DRR_base_section_simple (Autodesk Fusion 360 design; units mm, degrees)
part number: 2026-11-05-15-11-21-307
part number: 2026-11-05-15-14-36-906
part number: 2026-11-05-15-14-36-939
part number: 2026-11-05-15-14-37-558
part number: 2026-11-05-15-14-38-707
part number: 2026-11-05-15-14-40-350
part number: 2026-11-05-15-14-40-384
part number: 2026-11-05-15-14-41-040
part number: 2026-11-05-15-14-42-462
Autodesk Fusion 360 part; units mm, degrees
sketch "Sketch1" plane through (0, 0, 0) normal (1, 0, 0) x (0, 0, -1) in component "Simple Core R"
  line L0 (-488, 329) -> (-588, 329)
  line L1 (-588, 329) -> (-588, 379)
  line L2 (-588, 379) -> (-488, 379)
  line L3 (-488, 379) -> (-488, 329)
  line L4 (-490, 331) -> (-586, 331)
  line L5 (-586, 331) -> (-586, 377)
  line L6 (-586, 377) -> (-490, 377)
  line L7 (-490, 377) -> (-490, 331)
  dimension "d249" = 329
  dimension "d251" = 379
  dimension "d253" = 331
  dimension "d255" = 377
  constraint horizontal L0.start L0.end
  constraint vertical L0.end L1.end
  constraint vertical L0.start L2.end
  constraint horizontal L1.end L2.end
  constraint horizontal L4.start L4.end
  constraint vertical L4.end L5.end
  constraint vertical L4.start L6.end
  constraint horizontal L5.end L6.end
  measures "d249" vertical distance of origin L0.start
  measures "d251" vertical distance of origin L1.end
  measures "d253" vertical distance of origin L4.start
  measures "d255" vertical distance of origin L5.end
extrude "Extrude1" add sketch "Sketch1" along normal blind 2000 makes body 1 in component "Simple Core R"
sketch "Sketch2" plane through (0, 0, 0) normal (0, 0, 1) x (1, 0, 0) in component "Simple Core R"
  circle A0 centre (50, 354) radius 5.5
  circle A1 centre (100, 354) radius 5.5
  dimension "d258" = 50
  dimension "d259" = 354
  dimension "d260" = 11
  dimension "d261" = 100
  dimension "d262" = 11
  constraint horizontal A0.centre A1.centre
  measures "d258" horizontal distance of origin A0.centre
  measures "d259" vertical distance of origin A0.centre
  measures "d260" diameter of A0
  measures "d261" horizontal distance of origin A1.centre
  measures "d262" diameter of A1
extrude "Extrude2" cut sketch "Sketch2" along normal blind 102 from surface at 487 bodies 1 in component "Simple Core R"
sketch "Sketch1 (2)" plane through (0, 0, 0) normal (1, 0, 0) x (0, 0, -1) in component "Simple Cap R"
  arc A0 (-694, 429) -> (-694, 279) centre (-228.25, 354) ccw
  line L0 (-694, 429) -> (-659, 429)
  line L1 (-659, 429) -> (-659, 382)
  line L2 (-659, 382) -> (-549, 382)
  line L3 (-549, 382) -> (-549, 326)
  line L4 (-549, 326) -> (-659, 326)
  line L5 (-659, 326) -> (-659, 279)
  line L6 (-659, 279) -> (-694, 279)
  dimension "d267" = 279
  dimension "d268" = 429
  dimension "d270" = 382
  dimension "d272" = 326
  dimension "d273" = 471.75
  constraint vertical A0.end A0.start
  constraint horizontal A0.start L0.end
  constraint vertical L0.end L1.end
  constraint horizontal L1.end L2.end
  constraint vertical L2.end L3.end
  constraint vertical L0.end L4.end
  constraint horizontal L3.end L4.end
  constraint vertical L0.end L5.end
  constraint horizontal A0.end L5.end
  measures "d267" vertical distance of origin A0.end
  measures "d268" vertical distance of origin A0.start
  measures "d270" vertical distance of origin L1.end
  measures "d272" vertical distance of origin L3.end
  measures "d273" radius of A0
extrude "Extrude1'" add sketch "Sketch1 (2)" along normal blind 1900 from surface at 100 separate body makes body 2 in component "Simple Cap R"
sketch "Sketch2 (2)" plane through (0, 0, 0) normal (1, 0, 0) x (0, 0, -1) in component "Simple Cap R"
  arc A0 (-691.4732, 426) -> (-691.4732, 282) centre (-225.25, 354) ccw
  line L0 (-691.4732, 426) -> (-659, 426)
  line L1 (-659, 426) -> (-659, 382)
  line L2 (-659, 382) -> (-549, 382)
  line L3 (-549, 382) -> (-549, 326)
  line L4 (-549, 326) -> (-659, 326)
  line L5 (-659, 326) -> (-659, 282)
  line L6 (-659, 282) -> (-691.4732, 282)
  dimension "d277" = 691.4732
  dimension "d278" = 282
  dimension "d279" = 426
  dimension "d281" = 382
  dimension "d283" = 326
  dimension "d284" = 471.75
  constraint vertical A0.end A0.start
  constraint horizontal A0.start L0.end
  constraint vertical L0.end L1.end
  constraint horizontal L1.end L2.end
  constraint vertical L2.end L3.end
  constraint vertical L0.end L4.end
  constraint horizontal L3.end L4.end
  constraint vertical L0.end L5.end
  constraint horizontal A0.end L5.end
  measures "d277" horizontal distance of origin A0.end
  measures "d278" vertical distance of origin A0.end
  measures "d279" vertical distance of origin A0.start
  measures "d281" vertical distance of origin L1.end
  measures "d283" vertical distance of origin L3.end
  measures "d284" radius of A0
extrude "Extrude2'" add sketch "Sketch2 (2)" along normal blind 100 bodies 2 in component "Simple Cap R"
sketch "Sketch3" plane through (0, 0, 0) normal (1, 0, 0) x (0, 0, -1) in component "Simple Cap R"
  line L0 (-548, 328) -> (-659, 328)
  line L1 (-659, 328) -> (-659, 380)
  line L2 (-659, 380) -> (-548, 380)
  line L3 (-548, 380) -> (-548, 328)
  dimension "d287" = 548
  dimension "d288" = 328
  dimension "d290" = 380
  constraint horizontal L0.start L0.end
  constraint vertical L0.end L1.end
  constraint vertical L0.start L2.end
  constraint horizontal L1.end L2.end
  measures "d287" horizontal distance of origin L0.start
  measures "d288" vertical distance of origin L0.start
  measures "d290" vertical distance of origin L1.end
extrude "Extrude3" cut sketch "Sketch3" along normal blind 2002 from surface at -1 bodies 2 in component "Simple Cap R"
sketch "Sketch1 (3)" plane through (0, 0, 0) normal (0, 0, 1) x (1, 0, 0) in component "Simple Frames R"
  line L0 (280, 334) -> (320, 334)
  line L1 (320, 334) -> (320, 374)
  line L2 (320, 374) -> (280, 374)
  line L3 (280, 374) -> (280, 334)
  dimension "d294" = 280
  dimension "d295" = 334
  dimension "d296" = 320
  dimension "d297" = 374
  constraint horizontal L0.start L0.end
  constraint vertical L0.end L1.end
  constraint vertical L0.start L2.end
  constraint horizontal L1.end L2.end
  measures "d294" horizontal distance of origin L0.start
  measures "d295" vertical distance of origin L0.start
  measures "d296" horizontal distance of origin L0.end
  measures "d297" vertical distance of origin L1.end
extrude "Extrude1''" add sketch "Sketch1 (3)" along normal blind 458 from surface at 30 separate body makes body 3 in component "Simple Frames R"
sketch "Sketch2 (3)" plane through (0, 0, 0) normal (0, 1, 0) x (1, 0, 0) in component "Simple Frames R"
  line L0 (280, -30) -> (320, -30)
  line L1 (320, -30) -> (320, -70)
  line L2 (320, -70) -> (280, -70)
  line L3 (280, -70) -> (280, -30)
  dimension "d301" = 280
  dimension "d303" = 320
  constraint horizontal L0.start L0.end
  constraint vertical L0.end L1.end
  constraint vertical L0.start L2.end
  constraint horizontal L1.end L2.end
  measures "d301" horizontal distance of origin L0.start
  measures "d303" horizontal distance of origin L0.end
extrude "Extrude2''" add sketch "Sketch2 (3)" along normal blind 353 from surface at 1 bodies 3 in component "Simple Frames R"
sketch "Sketch3 (2)" plane through (0, 0, 0) normal (0, 0, 1) x (1, 0, 0) in component "Simple Frames R"
  circle A0 centre (300, 354) radius 40
  dimension "d309" = 354
  dimension "d310" = 80
  measures "d309" vertical distance of origin A0.centre
  measures "d310" diameter of A0
extrude "Extrude3'" add sketch "Sketch3 (2)" along normal blind 30 separate body makes body 4 in component "Simple Frames R"
sketch "Sketch4" plane through (0, 0, 0) normal (0, 0, 1) x (1, 0, 0) in component "Simple Frames R"
  line L0 (1680, 334) -> (1720, 334)
  line L1 (1720, 334) -> (1720, 374)
  line L2 (1720, 374) -> (1680, 374)
  line L3 (1680, 374) -> (1680, 334)
  dimension "d313" = 1680
  dimension "d314" = 334
  dimension "d315" = 1720
  dimension "d316" = 374
  constraint horizontal L0.start L0.end
  constraint vertical L0.end L1.end
  constraint vertical L0.start L2.end
  constraint horizontal L1.end L2.end
  measures "d313" horizontal distance of origin L0.start
  measures "d314" vertical distance of origin L0.start
  measures "d315" horizontal distance of origin L0.end
  measures "d316" vertical distance of origin L1.end
extrude "Extrude4" add sketch "Sketch4" along normal blind 458 from surface at 30 separate body makes body 5 in component "Simple Frames R"
sketch "Sketch5" plane through (0, 0, 0) normal (0, 1, 0) x (1, 0, 0) in component "Simple Frames R"
  line L0 (1680, -30) -> (1720, -30)
  line L1 (1720, -30) -> (1720, -70)
  line L2 (1720, -70) -> (1680, -70)
  line L3 (1680, -70) -> (1680, -30)
  dimension "d320" = 1680
  dimension "d322" = 1720
  constraint horizontal L0.start L0.end
  constraint vertical L0.end L1.end
  constraint vertical L0.start L2.end
  constraint horizontal L1.end L2.end
  measures "d320" horizontal distance of origin L0.start
  measures "d322" horizontal distance of origin L0.end
extrude "Extrude5" add sketch "Sketch5" along normal blind 353 from surface at 1 bodies 5 in component "Simple Frames R"
sketch "Sketch6" plane through (0, 0, 0) normal (0, 0, 1) x (1, 0, 0) in component "Simple Frames R"
  circle A0 centre (1700, 354) radius 40
  dimension "d328" = 354
  dimension "d329" = 80
  measures "d328" vertical distance of origin A0.centre
  measures "d329" diameter of A0
extrude "Extrude6" add sketch "Sketch6" along normal blind 30 separate body makes body 6 in component "Simple Frames R"
sketch "Sketch1 (4)" plane through (0, 0, 0) normal (1, 0, 0) x (0, 0, -1) in component "Simple Core L"
  line L0 (-488, -329) -> (-588, -329)
  line L1 (-588, -329) -> (-588, -379)
  line L2 (-588, -379) -> (-488, -379)
  line L3 (-488, -379) -> (-488, -329)
  line L4 (-490, -331) -> (-586, -331)
  line L5 (-586, -331) -> (-586, -377)
  line L6 (-586, -377) -> (-490, -377)
  line L7 (-490, -377) -> (-490, -331)
  dimension "d333" = 329
  dimension "d335" = 379
  dimension "d337" = 331
  dimension "d339" = 377
  constraint horizontal L0.start L0.end
  constraint vertical L0.end L1.end
  constraint vertical L0.start L2.end
  constraint horizontal L1.end L2.end
  constraint horizontal L4.start L4.end
  constraint vertical L4.end L5.end
  constraint vertical L4.start L6.end
  constraint horizontal L5.end L6.end
  measures "d333" vertical distance of origin L0.start
  measures "d335" vertical distance of origin L1.end
  measures "d337" vertical distance of origin L4.start
  measures "d339" vertical distance of origin L5.end
extrude "Extrude1'''" add sketch "Sketch1 (4)" along normal blind 2000 separate body makes body 7 in component "Simple Core L"
sketch "Sketch2 (4)" plane through (0, 0, 0) normal (0, 0, 1) x (1, 0, 0) in component "Simple Core L"
  circle A0 centre (50, -354) radius 5.5
  circle A1 centre (100, -354) radius 5.5
  dimension "d342" = 50
  dimension "d343" = 354
  dimension "d344" = 11
  dimension "d345" = 100
  dimension "d346" = 11
  constraint horizontal A0.centre A1.centre
  measures "d342" horizontal distance of origin A0.centre
  measures "d343" vertical distance of origin A0.centre
  measures "d344" diameter of A0
  measures "d345" horizontal distance of origin A1.centre
  measures "d346" diameter of A1
extrude "Extrude2'''" cut sketch "Sketch2 (4)" along normal blind 102 from surface at 487 bodies 7 in component "Simple Core L"
sketch "Sketch1 (5)" plane through (0, 0, 0) normal (1, 0, 0) x (0, 0, -1) in component "Simple Cap L"
  arc A0 (-694, -279) -> (-694, -429) centre (-228.25, -354) ccw
  line L0 (-694, -279) -> (-659, -279)
  line L1 (-659, -279) -> (-659, -326)
  line L2 (-659, -326) -> (-549, -326)
  line L3 (-549, -326) -> (-549, -382)
  line L4 (-549, -382) -> (-659, -382)
  line L5 (-659, -382) -> (-659, -429)
  line L6 (-659, -429) -> (-694, -429)
  dimension "d351" = 429
  dimension "d352" = 279
  dimension "d354" = 326
  dimension "d356" = 382
  dimension "d357" = 471.75
  constraint vertical A0.end A0.start
  constraint horizontal A0.start L0.end
  constraint vertical L0.end L1.end
  constraint horizontal L1.end L2.end
  constraint vertical L2.end L3.end
  constraint vertical L0.end L4.end
  constraint horizontal L3.end L4.end
  constraint vertical L0.end L5.end
  constraint horizontal A0.end L5.end
  measures "d351" vertical distance of origin A0.end
  measures "d352" vertical distance of origin A0.start
  measures "d354" vertical distance of origin L1.end
  measures "d356" vertical distance of origin L3.end
  measures "d357" radius of A0
extrude "Extrude1''''" add sketch "Sketch1 (5)" along normal blind 1900 from surface at 100 separate body makes body 8 in component "Simple Cap L"
sketch "Sketch2 (5)" plane through (0, 0, 0) normal (1, 0, 0) x (0, 0, -1) in component "Simple Cap L"
  arc A0 (-691.4732, -282) -> (-691.4732, -426) centre (-225.25, -354) ccw
  line L0 (-691.4732, -282) -> (-659, -282)
  line L1 (-659, -282) -> (-659, -326)
  line L2 (-659, -326) -> (-549, -326)
  line L3 (-549, -326) -> (-549, -382)
  line L4 (-549, -382) -> (-659, -382)
  line L5 (-659, -382) -> (-659, -426)
  line L6 (-659, -426) -> (-691.4732, -426)
  dimension "d361" = 691.4732
  dimension "d362" = 426
  dimension "d363" = 282
  dimension "d365" = 326
  dimension "d367" = 382
  dimension "d368" = 471.75
  constraint vertical A0.end A0.start
  constraint horizontal A0.start L0.end
  constraint vertical L0.end L1.end
  constraint horizontal L1.end L2.end
  constraint vertical L2.end L3.end
  constraint vertical L0.end L4.end
  constraint horizontal L3.end L4.end
  constraint vertical L0.end L5.end
  constraint horizontal A0.end L5.end
  measures "d361" horizontal distance of origin A0.end
  measures "d362" vertical distance of origin A0.end
  measures "d363" vertical distance of origin A0.start
  measures "d365" vertical distance of origin L1.end
  measures "d367" vertical distance of origin L3.end
  measures "d368" radius of A0
extrude "Extrude2''''" add sketch "Sketch2 (5)" along normal blind 100 bodies 8 in component "Simple Cap L"
sketch "Sketch3 (3)" plane through (0, 0, 0) normal (1, 0, 0) x (0, 0, -1) in component "Simple Cap L"
  line L0 (-548, -328) -> (-659, -328)
  line L1 (-659, -328) -> (-659, -380)
  line L2 (-659, -380) -> (-548, -380)
  line L3 (-548, -380) -> (-548, -328)
  dimension "d371" = 548
  dimension "d372" = 328
  dimension "d374" = 380
  constraint horizontal L0.start L0.end
  constraint vertical L0.end L1.end
  constraint vertical L0.start L2.end
  constraint horizontal L1.end L2.end
  measures "d371" horizontal distance of origin L0.start
  measures "d372" vertical distance of origin L0.start
  measures "d374" vertical distance of origin L1.end
extrude "Extrude3''" cut sketch "Sketch3 (3)" along normal blind 2002 from surface at -1 bodies 8 in component "Simple Cap L"
sketch "Sketch1 (6)" plane through (0, 0, 0) normal (0, 0, 1) x (1, 0, 0) in component "Simple Frames L"
  line L0 (280, -374) -> (320, -374)
  line L1 (320, -374) -> (320, -334)
  line L2 (320, -334) -> (280, -334)
  line L3 (280, -334) -> (280, -374)
  dimension "d378" = 280
  dimension "d379" = 374
  dimension "d380" = 320
  dimension "d381" = 334
  constraint horizontal L0.start L0.end
  constraint vertical L0.end L1.end
  constraint vertical L0.start L2.end
  constraint horizontal L1.end L2.end
  measures "d378" horizontal distance of origin L0.start
  measures "d379" vertical distance of origin L0.start
  measures "d380" horizontal distance of origin L0.end
  measures "d381" vertical distance of origin L1.end
extrude "Extrude1'''''" add sketch "Sketch1 (6)" along normal blind 458 from surface at 30 separate body makes body 9 in component "Simple Frames L"
sketch "Sketch2 (6)" plane through (0, 0, 0) normal (0, 1, 0) x (1, 0, 0) in component "Simple Frames L"
  line L0 (280, -30) -> (320, -30)
  line L1 (320, -30) -> (320, -70)
  line L2 (320, -70) -> (280, -70)
  line L3 (280, -70) -> (280, -30)
  dimension "d385" = 280
  dimension "d387" = 320
  constraint horizontal L0.start L0.end
  constraint vertical L0.end L1.end
  constraint vertical L0.start L2.end
  constraint horizontal L1.end L2.end
  measures "d385" horizontal distance of origin L0.start
  measures "d387" horizontal distance of origin L0.end
extrude "Extrude2'''''" add sketch "Sketch2 (6)" along normal blind 353 from surface at -354 bodies 9 in component "Simple Frames L"
sketch "Sketch3 (4)" plane through (0, 0, 0) normal (0, 0, 1) x (1, 0, 0) in component "Simple Frames L"
  circle A0 centre (300, -354) radius 40
  dimension "d393" = 354
  dimension "d394" = 80
  measures "d393" vertical distance of origin A0.centre
  measures "d394" diameter of A0
extrude "Extrude3'''" add sketch "Sketch3 (4)" along normal blind 30 separate body makes body 10 in component "Simple Frames L"
sketch "Sketch4 (2)" plane through (0, 0, 0) normal (0, 0, 1) x (1, 0, 0) in component "Simple Frames L"
  line L0 (1680, -374) -> (1720, -374)
  line L1 (1720, -374) -> (1720, -334)
  line L2 (1720, -334) -> (1680, -334)
  line L3 (1680, -334) -> (1680, -374)
  dimension "d397" = 1680
  dimension "d398" = 374
  dimension "d399" = 1720
  dimension "d400" = 334
  constraint horizontal L0.start L0.end
  constraint vertical L0.end L1.end
  constraint vertical L0.start L2.end
  constraint horizontal L1.end L2.end
  measures "d397" horizontal distance of origin L0.start
  measures "d398" vertical distance of origin L0.start
  measures "d399" horizontal distance of origin L0.end
  measures "d400" vertical distance of origin L1.end
extrude "Extrude4'" add sketch "Sketch4 (2)" along normal blind 458 from surface at 30 separate body makes body 11 in component "Simple Frames L"
sketch "Sketch5 (2)" plane through (0, 0, 0) normal (0, 1, 0) x (1, 0, 0) in component "Simple Frames L"
  line L0 (1680, -30) -> (1720, -30)
  line L1 (1720, -30) -> (1720, -70)
  line L2 (1720, -70) -> (1680, -70)
  line L3 (1680, -70) -> (1680, -30)
  dimension "d404" = 1680
  dimension "d406" = 1720
  constraint horizontal L0.start L0.end
  constraint vertical L0.end L1.end
  constraint vertical L0.start L2.end
  constraint horizontal L1.end L2.end
  measures "d404" horizontal distance of origin L0.start
  measures "d406" horizontal distance of origin L0.end
extrude "Extrude5'" add sketch "Sketch5 (2)" along normal blind 353 from surface at -354 bodies 11 in component "Simple Frames L"
sketch "Sketch6 (2)" plane through (0, 0, 0) normal (0, 0, 1) x (1, 0, 0) in component "Simple Frames L"
  circle A0 centre (1700, -354) radius 40
  dimension "d412" = 354
  dimension "d413" = 80
  measures "d412" vertical distance of origin A0.centre
  measures "d413" diameter of A0
extrude "Extrude6'" add sketch "Sketch6 (2)" along normal blind 30 separate body makes body 12 in component "Simple Frames L"
component "Simple Half R" placed x (1, 0, 0) y (0, 1, 0) z (0, 0, 1) at (0, 0, 0)
component "Simple Half L" placed x (1, 0, 0) y (0, 1, 0) z (0, 0, 1) at (0, 0, 0)
component "Simple Core R" placed x (1, 0, 0) y (0, 1, 0) z (0, 0, 1) at (0, 0, 0) in component "Simple Half R"
component "Simple Cap R" placed x (1, 0, 0) y (0, 1, 0) z (0, 0, 1) at (0, 0, 0) in component "Simple Half R"
component "Simple Frames R" placed x (1, 0, 0) y (0, 1, 0) z (0, 0, 1) at (0, 0, 0) in component "Simple Half R"
component "Simple Core L" placed x (1, 0, 0) y (0, 1, 0) z (0, 0, 1) at (0, 0, 0) in component "Simple Half L"
component "Simple Cap L" placed x (1, 0, 0) y (0, 1, 0) z (0, 0, 1) at (0, 0, 0) in component "Simple Half L"
component "Simple Frames L" placed x (1, 0, 0) y (0, 1, 0) z (0, 0, 1) at (0, 0, 0) in component "Simple Half L"
equation "drone_mass = 140.6 kg" comment "spec: drone mass (310 lb)"
equation "wingspan = 6100 mm" comment "spec: stand-in wingspan (20 ft)"
equation "body_width = 508 mm" comment "spec: body width, design value"
equation "body_drop = 254 mm" comment "spec: wing underside to body bottom"
equation "prop_dia = 700 mm" comment "spec: prop diameter, stopped blades vertical"
equation "tail_clear = 330 mm" comment "spec: tail underside above wing underside (drone requirement, 5 deg landing pitch)"
equation "landing_speed_kn = 40" comment "spec: landing speed, knots"
equation "sink_rate_ms = 1.5" comment "spec: sink rate at touchdown, m/s"
equation "grip = 0.3" comment "spec: friction coefficient, cap on wing"
equation "max_offset = 300 mm" comment "spec: side-to-side landing error"
equation "side_clear = 25 mm" comment "spec: gap between body and cap each side"
equation "rail_gap = body_width + 2 * side_clear" comment "spec: inner gap between caps"
equation "cap_width = 150 mm" comment "spec"
equation "cap_wall = 2 mm" comment "spec (was 3 mm; 2 mm for the 25 kg target)"
equation "cap_overlap = 100 mm" comment "spec: shingle overlap at joints"
equation "core_w = 50 mm" comment "spec: aluminium core tube width"
equation "core_h = 100 mm" comment "spec: aluminium core tube height"
equation "core_wall = 2 mm" comment "spec (was 3 mm; 2 mm for the 25 kg target)"
equation "rail_top_h = 700 mm" comment "spec: ground to cap top, unloaded"
equation "section_len = 2000 mm" comment "spec (was 2400 mm; 2000 mm for the 25 kg target)"
equation "frame_inset = 300 mm" comment "spec: U-frame position from section end"
equation "spring_travel = 50 mm" comment "spec"
equation "spring_rate = 90" comment "spec: N/mm per wing contact point"
equation "springs_per_cap = 2" comment "spec"
equation "section_count = 30" comment "spec: sections for the run length"
equation "model_scale = 0.1" comment "spec: printable model scale"
equation "body_len = 4000 mm" comment "spec sec 2 (assumed): stand-in body length"
equation "wing_chord = 600 mm" comment "spec sec 2 (assumed): stand-in wing chord"
equation "wing_thk = 80 mm" comment "assumed: stand-in wing thickness"
equation "tail_arm = 3000 mm" comment "assumed (spec risk 1): wing mid-chord to tail"
equation "tail_span = 1800 mm" comment "assumed: horizontal tail span"
equation "tail_chord = 400 mm" comment "assumed"
equation "tail_thk = 30 mm" comment "assumed"
equation "prop_blade_w = 60 mm" comment "assumed: blade width"
equation "prop_blade_t = 20 mm" comment "assumed"
equation "prop_disc_t = 4 mm" comment "prop disc stand-in thickness"
equation "rail_cc = rail_gap + cap_width" comment "derived: rail centre-to-centre"
equation "cap_crown = 6 mm" comment "assumed: crown rise across the cap"
equation "cap_flange_d = 35 mm" comment "assumed: cap flange depth at the edges"
equation "cap_nose_r = 25 mm" comment "assumed: rounded nose radius, upstream end"
equation "cap_tail_r = 1.5 mm" comment "assumed: edge radius, downstream (top shingle) end; below cap_wall"
equation "cap_gap = 1 mm" comment "assumed: skirt-to-core and shingle nesting gap"
equation "spring_len = 110 mm" comment "assumed: installed spring length, unloaded"
equation "spring_od = 40 mm" comment "assumed"
equation "spring_wire = 6 mm" comment "assumed"
equation "spring_coils = 8" comment "assumed: coil turns"
equation "screw_d = 8 mm" comment "assumed: M8 guide screw"
equation "screw_head_d = 16 mm" comment "assumed"
equation "screw_head_t = 5 mm" comment "assumed"
equation "screw_drop = 25 mm" comment "assumed: screw axis below core top"
equation "skirt_margin = 10 mm" comment "assumed: skirt below slot bottom"
equation "slot_clear = 1 mm" comment "assumed: slot width over screw"
equation "tongue_len = 300 mm" comment "assumed: splice tongue, half protrudes"
equation "slide_fit = 0.5 mm" comment "assumed: sliding clearance, full scale"
equation "pin_d = 10 mm" comment "assumed: ball-lock pin"
equation "pin_head_d = 25 mm" comment "assumed"
equation "pin_head_t = 8 mm" comment "assumed"
equation "pin_x1 = 50 mm" comment "assumed: pin positions past the joint"
equation "pin_x2 = 100 mm" comment "assumed"
equation "frame_tube = 40 mm" comment "assumed: U-frame square tube"
equation "frame_wall = 3 mm" comment "assumed"
equation "split_gap = 2 mm" comment "assumed: gap at the U-frame split"
equation "xbar_splice = 60 mm" comment "assumed: cross-bar splice tongue reach"
equation "frame_pin_d = 12 mm" comment "assumed: U-frame split pin"
equation "foot_h = 30 mm" comment "assumed: ground to frame underside"
equation "foot_plate_w = 150 mm" comment "assumed: bolt-down plate"
equation "foot_plate_t = 8 mm" comment "assumed"
equation "foot_bolt_d = 13 mm" comment "assumed"
equation "foot_bolt_pitch = 110 mm" comment "assumed"
equation "foot_pad_d = 80 mm" comment "assumed"
equation "foot_pad_t = 10 mm" comment "assumed"
equation "foot_stud_d = 16 mm" comment "assumed: M16 levelling stud"
equation "core_top_z = rail_top_h - cap_wall - spring_len" comment "derived"
equation "core_bot_z = core_top_z - core_h" comment "derived"
equation "screw_z = core_top_z - screw_drop" comment "derived"
equation "skirt_bot_z = screw_z - screw_d / 2 - skirt_margin" comment "derived"
equation "flange_bot_z = rail_top_h - cap_crown - cap_flange_d" comment "derived"
equation "skirt_out = core_w / 2 + cap_gap + cap_wall" comment "derived: skirt outer face from core centre"
equation "xbar_top_z = foot_h + frame_tube" comment "derived: cross-bar top (spec: 80 mm max)"
equation "d248 = ( core_bot_z )"
equation "d249 = ( ( ( rail_cc / 2 ) ) + ( -core_w / 2 ) )"
equation "d250 = ( core_top_z )"
equation "d251 = ( ( ( rail_cc / 2 ) ) + ( core_w / 2 ) )"
equation "d252 = ( core_bot_z + core_wall )"
equation "d253 = ( ( ( rail_cc / 2 ) ) + ( -( core_w / 2 - core_wall ) ) )"
equation "d254 = ( core_top_z - core_wall )"
equation "d255 = ( ( ( rail_cc / 2 ) ) + ( core_w / 2 - core_wall ) )"
equation "d256 = ( section_len ) - ( 0 mm )"
equation "d258 = ( pin_x1 )"
equation "d259 = ( ( rail_cc / 2 ) )"
equation "d260 = pin_d + 2 * slide_fit"
equation "d261 = ( pin_x2 )"
equation "d262 = pin_d + 2 * slide_fit"
equation "d263 = core_bot_z - 1 mm"
equation "d264 = ( core_top_z + 1 mm ) - ( core_bot_z - 1 mm )"
equation "d266 = ( ( rail_top_h - cap_crown ) )"
equation "d267 = ( ( ( ( ( rail_cc / 2 ) ) + ( 0 mm ) ) - ( ( cap_width ) / 2 ) ) )"
equation "d268 = ( ( ( ( ( rail_cc / 2 ) ) + ( 0 mm ) ) + ( ( cap_width ) / 2 ) ) )"
equation "d269 = ( flange_bot_z )"
equation "d270 = ( ( ( ( rail_cc / 2 ) ) + skirt_out ) )"
equation "d271 = ( skirt_bot_z )"
equation "d272 = ( ( ( ( rail_cc / 2 ) ) - skirt_out ) )"
equation "d273 = ( ( ( ( cap_width ) / 2 ) ^ 2 + cap_crown ^ 2 ) / ( 2 * cap_crown ) )"
equation "d274 = cap_overlap"
equation "d275 = ( section_len ) - ( cap_overlap )"
equation "d277 = ( ( rail_top_h - ( cap_wall + cap_gap ) - ( ( ( ( ( cap_width ) / 2 ) ^ 2 + cap_crown ^ 2 ) / ( 2 * cap_crown ) ) - sqrt(( ( ( ( cap_width ) / 2 ) ^ 2 + cap_crown ^ 2 ) / ( 2 * cap_crown ) ) ^ 2 - ( ( ( cap_width ) / 2 ) - ( cap_wall + cap_gap ) ) ^ 2) ) ) )"
equation "d278 = ( ( ( ( ( rail_cc / 2 ) ) + ( 0 mm ) ) - ( ( ( cap_width ) / 2 ) - ( cap_wall + cap_gap ) ) ) )"
equation "d279 = ( ( ( ( ( rail_cc / 2 ) ) + ( 0 mm ) ) + ( ( ( cap_width ) / 2 ) - ( cap_wall + cap_gap ) ) ) )"
equation "d280 = ( flange_bot_z )"
equation "d281 = ( ( ( ( rail_cc / 2 ) ) + skirt_out ) )"
equation "d282 = ( skirt_bot_z )"
equation "d283 = ( ( ( ( rail_cc / 2 ) ) - skirt_out ) )"
equation "d284 = ( ( ( ( cap_width ) / 2 ) ^ 2 + cap_crown ^ 2 ) / ( 2 * cap_crown ) )"
equation "d285 = ( cap_overlap ) - ( 0 mm )"
equation "d287 = ( skirt_bot_z - 1 mm )"
equation "d288 = ( ( ( rail_cc / 2 ) ) + ( -( core_w / 2 + cap_gap ) ) )"
equation "d289 = ( flange_bot_z )"
equation "d290 = ( ( ( rail_cc / 2 ) ) + ( core_w / 2 + cap_gap ) )"
equation "d292 = ( section_len + 1 mm ) - ( -1 mm )"
equation "d294 = ( ( frame_inset ) - frame_tube / 2 )"
equation "d295 = ( ( ( rail_cc / 2 ) ) - frame_tube / 2 )"
equation "d296 = ( ( frame_inset ) + frame_tube / 2 )"
equation "d297 = ( ( ( rail_cc / 2 ) ) + frame_tube / 2 )"
equation "d298 = foot_h"
equation "d299 = ( core_bot_z ) - ( foot_h )"
equation "d301 = ( ( frame_inset ) - frame_tube / 2 )"
equation "d302 = ( foot_h )"
equation "d303 = ( ( frame_inset ) + frame_tube / 2 )"
equation "d304 = ( xbar_top_z )"
equation "d305 = split_gap / 2"
equation "d306 = ( ( rail_cc / 2 ) ) - ( split_gap / 2 )"
equation "d308 = ( frame_inset )"
equation "d309 = ( ( rail_cc / 2 ) )"
equation "d310 = foot_pad_d"
equation "d311 = ( foot_h ) - ( 0 mm )"
equation "d313 = ( ( section_len - frame_inset ) - frame_tube / 2 )"
equation "d314 = ( ( ( rail_cc / 2 ) ) - frame_tube / 2 )"
equation "d315 = ( ( section_len - frame_inset ) + frame_tube / 2 )"
equation "d316 = ( ( ( rail_cc / 2 ) ) + frame_tube / 2 )"
equation "d317 = foot_h"
equation "d318 = ( core_bot_z ) - ( foot_h )"
equation "d320 = ( ( section_len - frame_inset ) - frame_tube / 2 )"
equation "d321 = ( foot_h )"
equation "d322 = ( ( section_len - frame_inset ) + frame_tube / 2 )"
equation "d323 = ( xbar_top_z )"
equation "d324 = split_gap / 2"
equation "d325 = ( ( rail_cc / 2 ) ) - ( split_gap / 2 )"
equation "d327 = ( section_len - frame_inset )"
equation "d328 = ( ( rail_cc / 2 ) )"
equation "d329 = foot_pad_d"
equation "d330 = ( foot_h ) - ( 0 mm )"
equation "d332 = ( core_bot_z )"
equation "d333 = -( ( -( rail_cc / 2 ) ) - ( -core_w / 2 ) )"
equation "d334 = ( core_top_z )"
equation "d335 = -( ( -( rail_cc / 2 ) ) - ( core_w / 2 ) )"
equation "d336 = ( core_bot_z + core_wall )"
equation "d337 = -( ( -( rail_cc / 2 ) ) - ( -( core_w / 2 - core_wall ) ) )"
equation "d338 = ( core_top_z - core_wall )"
equation "d339 = -( ( -( rail_cc / 2 ) ) - ( core_w / 2 - core_wall ) )"
equation "d340 = ( section_len ) - ( 0 mm )"
equation "d342 = ( pin_x1 )"
equation "d343 = -( -( rail_cc / 2 ) )"
equation "d344 = pin_d + 2 * slide_fit"
equation "d345 = ( pin_x2 )"
equation "d346 = pin_d + 2 * slide_fit"
equation "d347 = core_bot_z - 1 mm"
equation "d348 = ( core_top_z + 1 mm ) - ( core_bot_z - 1 mm )"
equation "d350 = ( ( rail_top_h - cap_crown ) )"
equation "d351 = -( ( ( ( -( rail_cc / 2 ) ) - ( 0 mm ) ) - ( ( cap_width ) / 2 ) ) )"
equation "d352 = -( ( ( ( -( rail_cc / 2 ) ) - ( 0 mm ) ) + ( ( cap_width ) / 2 ) ) )"
equation "d353 = ( flange_bot_z )"
equation "d354 = -( ( ( -( rail_cc / 2 ) ) + skirt_out ) )"
equation "d355 = ( skirt_bot_z )"
equation "d356 = -( ( ( -( rail_cc / 2 ) ) - skirt_out ) )"
equation "d357 = ( ( ( ( cap_width ) / 2 ) ^ 2 + cap_crown ^ 2 ) / ( 2 * cap_crown ) )"
equation "d358 = cap_overlap"
equation "d359 = ( section_len ) - ( cap_overlap )"
equation "d361 = ( ( rail_top_h - ( cap_wall + cap_gap ) - ( ( ( ( ( cap_width ) / 2 ) ^ 2 + cap_crown ^ 2 ) / ( 2 * cap_crown ) ) - sqrt(( ( ( ( cap_width ) / 2 ) ^ 2 + cap_crown ^ 2 ) / ( 2 * cap_crown ) ) ^ 2 - ( ( ( cap_width ) / 2 ) - ( cap_wall + cap_gap ) ) ^ 2) ) ) )"
equation "d362 = -( ( ( ( -( rail_cc / 2 ) ) - ( 0 mm ) ) - ( ( ( cap_width ) / 2 ) - ( cap_wall + cap_gap ) ) ) )"
equation "d363 = -( ( ( ( -( rail_cc / 2 ) ) - ( 0 mm ) ) + ( ( ( cap_width ) / 2 ) - ( cap_wall + cap_gap ) ) ) )"
equation "d364 = ( flange_bot_z )"
equation "d365 = -( ( ( -( rail_cc / 2 ) ) + skirt_out ) )"
equation "d366 = ( skirt_bot_z )"
equation "d367 = -( ( ( -( rail_cc / 2 ) ) - skirt_out ) )"
equation "d368 = ( ( ( ( cap_width ) / 2 ) ^ 2 + cap_crown ^ 2 ) / ( 2 * cap_crown ) )"
equation "d369 = ( cap_overlap ) - ( 0 mm )"
equation "d371 = ( skirt_bot_z - 1 mm )"
equation "d372 = -( ( -( rail_cc / 2 ) ) - ( -( core_w / 2 + cap_gap ) ) )"
equation "d373 = ( flange_bot_z )"
equation "d374 = -( ( -( rail_cc / 2 ) ) - ( core_w / 2 + cap_gap ) )"
equation "d376 = ( section_len + 1 mm ) - ( -1 mm )"
equation "d378 = ( ( frame_inset ) - frame_tube / 2 )"
equation "d379 = -( ( -( rail_cc / 2 ) ) - frame_tube / 2 )"
equation "d380 = ( ( frame_inset ) + frame_tube / 2 )"
equation "d381 = -( ( -( rail_cc / 2 ) ) + frame_tube / 2 )"
equation "d382 = foot_h"
equation "d383 = ( core_bot_z ) - ( foot_h )"
equation "d385 = ( ( frame_inset ) - frame_tube / 2 )"
equation "d386 = ( foot_h )"
equation "d387 = ( ( frame_inset ) + frame_tube / 2 )"
equation "d388 = ( xbar_top_z )"
equation "d389 = -( rail_cc / 2 )"
equation "d390 = ( -split_gap / 2 ) - ( -( rail_cc / 2 ) )"
equation "d392 = ( frame_inset )"
equation "d393 = -( -( rail_cc / 2 ) )"
equation "d394 = foot_pad_d"
equation "d395 = ( foot_h ) - ( 0 mm )"
equation "d397 = ( ( section_len - frame_inset ) - frame_tube / 2 )"
equation "d398 = -( ( -( rail_cc / 2 ) ) - frame_tube / 2 )"
equation "d399 = ( ( section_len - frame_inset ) + frame_tube / 2 )"
equation "d400 = -( ( -( rail_cc / 2 ) ) + frame_tube / 2 )"
equation "d401 = foot_h"
equation "d402 = ( core_bot_z ) - ( foot_h )"
equation "d404 = ( ( section_len - frame_inset ) - frame_tube / 2 )"
equation "d405 = ( foot_h )"
equation "d406 = ( ( section_len - frame_inset ) + frame_tube / 2 )"
equation "d407 = ( xbar_top_z )"
equation "d408 = -( rail_cc / 2 )"
equation "d409 = ( -split_gap / 2 ) - ( -( rail_cc / 2 ) )"
equation "d411 = ( section_len - frame_inset )"
equation "d412 = -( -( rail_cc / 2 ) )"
equation "d413 = foot_pad_d"
equation "d414 = ( foot_h ) - ( 0 mm )"
named bodies: "Core R", "Cap R", "Frame R1", "Foot R1", "Frame R2", "Foot R2", "Core L", "Cap L", "Frame L1", "Foot L1", "Frame L2", "Foot L2"
